Autodesk Fusion 360 part; units mm, degrees
(part 9 of 9)
equation "d1122 = abs(hubHoleSpacing / sqrt(2))"
equation "d1126 = hubFace - adapterThickness - 1 mm"
equation "d1128 = abs(hubHoleSpacing / sqrt(2))"
equation "d1133 = hubFace - adapterThickness - 1 mm"
equation "d1135 = abs(hubHoleSpacing / sqrt(2))"
equation "d1139 = hubFace - adapterThickness - 5 mm"
equation "d1141 = abs(hubHoleSpacing / sqrt(2))"
equation "d1145 = hubFace - adapterThickness - 1 mm"
equation "d1147 = abs(hubHoleSpacing / sqrt(2))"
equation "d1152 = hubFace - adapterThickness - 1 mm"
equation "d1154 = abs(-hubHoleSpacing / sqrt(2))"
equation "d1158 = hubFace - adapterThickness - 5 mm"
equation "d1160 = abs(-hubHoleSpacing / sqrt(2))"
equation "d1164 = hubFace - adapterThickness - 1 mm"
equation "d1166 = abs(-hubHoleSpacing / sqrt(2))"
equation "d1171 = hubFace - adapterThickness - 1 mm"
equation "d1173 = abs(-hubHoleSpacing / sqrt(2))"
equation "d1177 = hubFace - adapterThickness - 5 mm"
equation "d1179 = abs(-hubHoleSpacing / sqrt(2))"
equation "d1183 = hubFace - adapterThickness - 1 mm"
equation "d1185 = abs(-hubHoleSpacing / sqrt(2))"
equation "d1190 = hubFace - adapterThickness - 1 mm"
equation "d1192 = abs(mountCircle / ( 2 * sqrt(2) ))"
equation "d1193 = abs(mountCircle / ( 2 * sqrt(2) ))"
equation "d1197 = hubFace - adapterThickness - 5 mm"
equation "d1199 = abs(mountCircle / ( 2 * sqrt(2) ))"
equation "d1200 = abs(mountCircle / ( 2 * sqrt(2) ))"
equation "d1204 = hubFace - adapterThickness - 1 mm"
equation "d1206 = abs(mountCircle / ( 2 * sqrt(2) ))"
equation "d1207 = abs(mountCircle / ( 2 * sqrt(2) ))"
equation "d1212 = -qFront - nutDepth"
equation "d1214 = abs(mountCircle / ( 2 * sqrt(2) ))"
equation "d1215 = abs(mountCircle / ( 2 * sqrt(2) ))"
equation "d1216 = 2 * ( 7 mm ) / sqrt(3)"
equation "d1219 = abs(mountCircle / ( 2 * sqrt(2) ))"
equation "d1220 = abs(mountCircle / ( 2 * sqrt(2) ))"
equation "d1224 = hubFace - adapterThickness - 1 mm"
equation "d1226 = abs(-mountCircle / ( 2 * sqrt(2) ))"
equation "d1227 = abs(mountCircle / ( 2 * sqrt(2) ))"
equation "d1231 = hubFace - adapterThickness - 5 mm"
equation "d1233 = abs(-mountCircle / ( 2 * sqrt(2) ))"
equation "d1234 = abs(mountCircle / ( 2 * sqrt(2) ))"
equation "d1238 = hubFace - adapterThickness - 1 mm"
equation "d1240 = abs(-mountCircle / ( 2 * sqrt(2) ))"
equation "d1241 = abs(mountCircle / ( 2 * sqrt(2) ))"
equation "d1246 = -qFront - nutDepth"
equation "d1248 = abs(-mountCircle / ( 2 * sqrt(2) ))"
equation "d1249 = abs(mountCircle / ( 2 * sqrt(2) ))"
equation "d1250 = 2 * ( 7 mm ) / sqrt(3)"
equation "d1253 = abs(-mountCircle / ( 2 * sqrt(2) ))"
equation "d1254 = abs(mountCircle / ( 2 * sqrt(2) ))"
equation "d1258 = hubFace - adapterThickness - 1 mm"
equation "d1260 = abs(-mountCircle / ( 2 * sqrt(2) ))"
equation "d1261 = abs(-mountCircle / ( 2 * sqrt(2) ))"
equation "d1265 = hubFace - adapterThickness - 5 mm"
equation "d1267 = abs(-mountCircle / ( 2 * sqrt(2) ))"
equation "d1268 = abs(-mountCircle / ( 2 * sqrt(2) ))"
equation "d1272 = hubFace - adapterThickness - 1 mm"
equation "d1274 = abs(-mountCircle / ( 2 * sqrt(2) ))"
equation "d1275 = abs(-mountCircle / ( 2 * sqrt(2) ))"
equation "d1280 = -qFront - nutDepth"
equation "d1282 = abs(-mountCircle / ( 2 * sqrt(2) ))"
equation "d1283 = abs(-mountCircle / ( 2 * sqrt(2) ))"
equation "d1284 = 2 * ( 7 mm ) / sqrt(3)"
equation "d1287 = abs(-mountCircle / ( 2 * sqrt(2) ))"
equation "d1288 = abs(-mountCircle / ( 2 * sqrt(2) ))"
equation "d1292 = hubFace - adapterThickness - 1 mm"
equation "d1294 = abs(mountCircle / ( 2 * sqrt(2) ))"
equation "d1295 = abs(-mountCircle / ( 2 * sqrt(2) ))"
equation "d1299 = hubFace - adapterThickness - 5 mm"
equation "d1301 = abs(mountCircle / ( 2 * sqrt(2) ))"
equation "d1302 = abs(-mountCircle / ( 2 * sqrt(2) ))"
equation "d1306 = hubFace - adapterThickness - 1 mm"
equation "d1308 = abs(mountCircle / ( 2 * sqrt(2) ))"
equation "d1309 = abs(-mountCircle / ( 2 * sqrt(2) ))"
equation "d1314 = -qFront - nutDepth"
equation "d1316 = abs(mountCircle / ( 2 * sqrt(2) ))"
equation "d1317 = abs(-mountCircle / ( 2 * sqrt(2) ))"
equation "d1318 = 2 * ( 7 mm ) / sqrt(3)"
equation "d1321 = abs(mountCircle / ( 2 * sqrt(2) ))"
equation "d1322 = abs(-mountCircle / ( 2 * sqrt(2) ))"
equation "d1329 = qRearEnd + capThickness + 0.5 mm - 45 mm"
equation "d1331 = supportCircle / 2"
equation "d1335 = qRearEnd + capThickness + 0.5 mm"
equation "d1337 = supportCircle / 2"
equation "d1341 = qRearEnd + capThickness"
equation "d1343 = supportCircle / 2"
equation "d1348 = qFront - capThickness - 0.5 mm"
equation "d1350 = supportCircle / 2"
equation "d1355 = qFront - capThickness - 4.5 mm"
equation "d1357 = supportCircle / 2"
equation "driverPort = 5 mm" comment "Clearance for bare3 mm hex-key shafts; bulky bit holders do not fit."
equation "accessPadWidth = 12 mm" comment "Reinforced access-port capsule width."
equation "accessPadExtra = 2 mm" comment "Local inward reinforcement beyond nominal side wall."
equation "d1369 = bodyWidth / 2"
equation "d1451 = abs(55 mm)"
equation "d1452 = abs(66.5 mm)"
equation "d1453 = abs(130 mm)"
equation "d1454 = abs(66.5 mm)"
equation "d1455 = abs(130 mm)"
equation "d1456 = abs(75 mm)"
equation "d1457 = abs(55 mm)"
equation "d1458 = abs(75 mm)"
equation "d1469 = abs(48 mm)"
equation "d1470 = abs(-35 mm)"
equation "d1471 = abs(130 mm)"
equation "d1472 = abs(-35 mm)"
equation "d1473 = abs(130 mm)"
equation "d1474 = abs(35 mm)"
equation "d1475 = abs(48 mm)"
equation "d1476 = abs(35 mm)"
equation "d1487 = bodyWidth / 2"
equation "d1489 = abs(( -1 ) * ( -bodyWidth / 2 + sqrt(2) * ( mountCircle / ( 2 * sqrt(2) ) ) ) + ( 0 ) * ( mountCircle / ( 2 * sqrt(2) ) ))"
equation "d1490 = abs(( 0 ) * ( -bodyWidth / 2 + sqrt(2) * ( mountCircle / ( 2 * sqrt(2) ) ) ) + ( 1 ) * ( mountCircle / ( 2 * sqrt(2) ) ))"
equation "d1493 = -( wall + accessPadExtra )"
equation "d1495 = abs(( -1 ) * ( -bodyWidth / 2 + sqrt(2) * ( mountCircle / ( 2 * sqrt(2) ) ) ) + ( 0 ) * ( -mountCircle / ( 2 * sqrt(2) ) ))"
equation "d1496 = abs(( 0 ) * ( -bodyWidth / 2 + sqrt(2) * ( mountCircle / ( 2 * sqrt(2) ) ) ) + ( 1 ) * ( -mountCircle / ( 2 * sqrt(2) ) ))"
equation "d1499 = -( wall + accessPadExtra )"
equation "d1501 = abs(( -1 ) * ( -bodyWidth / 2 + sqrt(2) * ( -mountCircle / ( 2 * sqrt(2) ) ) ) + ( 0 ) * ( -mountCircle / ( 2 * sqrt(2) ) ))"
equation "d1502 = abs(( 0 ) * ( -bodyWidth / 2 + sqrt(2) * ( -mountCircle / ( 2 * sqrt(2) ) ) ) + ( 1 ) * ( -mountCircle / ( 2 * sqrt(2) ) ))"
equation "d1505 = -( wall + accessPadExtra )"
equation "d1507 = abs(( -1 ) * ( -bodyWidth / 2 + sqrt(2) * ( -mountCircle / ( 2 * sqrt(2) ) ) ) + ( 0 ) * ( mountCircle / ( 2 * sqrt(2) ) ))"
equation "d1508 = abs(( 0 ) * ( -bodyWidth / 2 + sqrt(2) * ( -mountCircle / ( 2 * sqrt(2) ) ) ) + ( 1 ) * ( mountCircle / ( 2 * sqrt(2) ) ))"
equation "d1511 = -( wall + accessPadExtra )"
equation "d1515 = abs(mountCircle / ( 2 * sqrt(2) ))"
equation "d1516 = abs(mountCircle / ( 2 * sqrt(2) ))"
equation "d1517 = driverPort"
equation "d1518 = abs(-mountCircle / ( 2 * sqrt(2) ))"
equation "d1519 = abs(mountCircle / ( 2 * sqrt(2) ))"
equation "d1520 = driverPort"
equation "d1521 = abs(-mountCircle / ( 2 * sqrt(2) ))"
equation "d1522 = abs(-mountCircle / ( 2 * sqrt(2) ))"
equation "d1523 = driverPort"
equation "d1524 = abs(mountCircle / ( 2 * sqrt(2) ))"
equation "d1525 = abs(-mountCircle / ( 2 * sqrt(2) ))"
equation "d1526 = driverPort"
equation "d1527 = -( bodyLength )"
equation "printEntryRelief = 0.3 mm" comment "Small nut, sleeve and free shaft-hole bed-mouth lead-in; not a bore size."
equation "d1530 = bedRelief"
equation "d1531 = bedRelief"
equation "d1532 = printEntryRelief"
equation "d1533 = printEntryRelief"
equation "d1534 = printEntryRelief"
named bodies: "A Housing print", "B Moving Body print", "A Housing print (1)"
